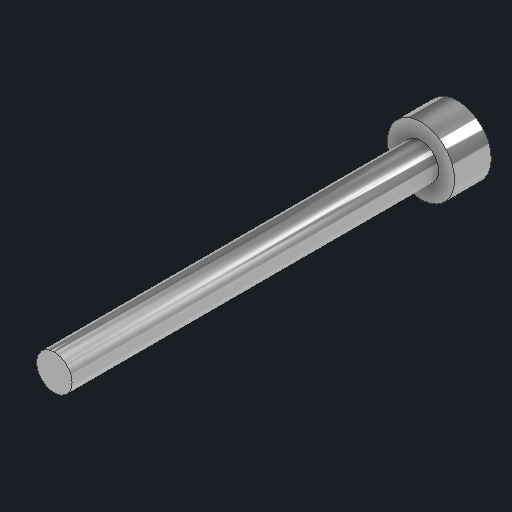
# Autodesk Inventor part: m3_shcs_30
Saved by Autodesk Inventor 2027.1 (Build 311270010, 270A)
## iProperties
Created: 2026-11-04
Part Number: m3_shcs_30
Material: Generic
Description: ISO 4762 socket head cap screw m3_shcs_30
Document SubType Name: Modeling
Designer: Claude (from photos)
Density: 1 g/cm^3
Appearance: Stainless Steel - Bright
Author: alexg
Autodesk Inventor part; units mm, degrees
ref_plane "YZ Plane" through (0, 0, 0) normal (1, 0, 0) x (0, 1, 0)
ref_plane "XZ Plane" through (0, 0, 0) normal (0, 1, 0) x (-1, 0, 0)
sketch "Head sketch" plane through (0, 0, 0) normal (0, 0, 1) x (1, 0, 0)
  circle A0 centre (0, 0) radius 2.75
  constraints: 1 centre point
extrude "Head" add sketch "Head sketch" against normal blind 3
ref_plane "Work Plane1" through (0, 0, -3) normal (0, 0, 1) x (1, 0, 0)
sketch "Hex socket sketch" plane through (0, 0, -3) normal (0, 0, 1) x (1, 0, 0)
  line L0 (0.9526, 0) -> (0.4763, 0.825)
  line L1 (0.4763, 0.825) -> (-0.4763, 0.825)
  line L2 (-0.4763, 0.825) -> (-0.9526, 0)
  line L3 (-0.9526, 0) -> (-0.4763, -0.825)
  line L4 (-0.4763, -0.825) -> (0.4763, -0.825)
  line L5 (0.4763, -0.825) -> (0.9526, 0)
  constraints: 12 end point
extrude "Hex socket" cut sketch "Hex socket sketch" along normal blind 1.8
sketch "Shank sketch" plane through (0, 0, 0) normal (0, 0, 1) x (1, 0, 0)
  circle A0 centre (0, 0) radius 1.45
  constraints: 1 centre point
extrude "Shank" add sketch "Shank sketch" along normal blind 30
body "Solid1"
